Autodesk Fusion 360 part; units mm, degrees
(part 2 of 2)
  circle A960 centre (51.0366, 22.3571) radius 0.5
  circle A961 centre (54.3293, 22.3571) radius 0.5
  circle A962 centre (57.622, 22.3571) radius 0.5
  circle A963 centre (60.9146, 22.3571) radius 0.5
  circle A964 centre (64.2073, 22.3571) radius 0.5
  circle A965 centre (67.5, 22.3571) radius 0.5
  circle A966 centre (-67.5, 25.2143) radius 0.5
  circle A967 centre (-64.2073, 25.2143) radius 0.5
  circle A968 centre (-60.9146, 25.2143) radius 0.5
  circle A969 centre (-57.622, 25.2143) radius 0.5
  circle A970 centre (-54.3293, 25.2143) radius 0.5
  circle A971 centre (-51.0366, 25.2143) radius 0.5
  circle A972 centre (-47.7439, 25.2143) radius 0.5
  circle A973 centre (-44.4512, 25.2143) radius 0.5
  circle A974 centre (-41.1585, 25.2143) radius 0.5
  circle A975 centre (-37.8659, 25.2143) radius 0.5
  circle A976 centre (-34.5732, 25.2143) radius 0.5
  circle A977 centre (-31.2805, 25.2143) radius 0.5
  circle A978 centre (-27.9878, 25.2143) radius 0.5
  circle A979 centre (-24.6951, 25.2143) radius 0.5
  circle A980 centre (-21.4024, 25.2143) radius 0.5
  circle A981 centre (-18.1098, 25.2143) radius 0.5
  circle A982 centre (-14.8171, 25.2143) radius 0.5
  circle A983 centre (-11.5244, 25.2143) radius 0.5
  circle A984 centre (-8.2317, 25.2143) radius 0.5
  circle A985 centre (-4.939, 25.2143) radius 0.5
  circle A986 centre (-1.6463, 25.2143) radius 0.5
  circle A987 centre (1.6463, 25.2143) radius 0.5
  circle A988 centre (4.939, 25.2143) radius 0.5
  circle A989 centre (8.2317, 25.2143) radius 0.5
  circle A990 centre (11.5244, 25.2143) radius 0.5
  circle A991 centre (14.8171, 25.2143) radius 0.5
  circle A992 centre (18.1098, 25.2143) radius 0.5
  circle A993 centre (21.4024, 25.2143) radius 0.5
  circle A994 centre (24.6951, 25.2143) radius 0.5
  circle A995 centre (27.9878, 25.2143) radius 0.5
  circle A996 centre (31.2805, 25.2143) radius 0.5
  circle A997 centre (34.5732, 25.2143) radius 0.5
  circle A998 centre (37.8659, 25.2143) radius 0.5
  circle A999 centre (41.1585, 25.2143) radius 0.5
  circle A1000 centre (44.4512, 25.2143) radius 0.5
  circle A1001 centre (47.7439, 25.2143) radius 0.5
  circle A1002 centre (51.0366, 25.2143) radius 0.5
  circle A1003 centre (54.3293, 25.2143) radius 0.5
  circle A1004 centre (57.622, 25.2143) radius 0.5
  circle A1005 centre (60.9146, 25.2143) radius 0.5
  circle A1006 centre (64.2073, 25.2143) radius 0.5
  circle A1007 centre (67.5, 25.2143) radius 0.5
  circle A1008 centre (-67.5, 28.0714) radius 0.5
  circle A1009 centre (-64.2073, 28.0714) radius 0.5
  circle A1010 centre (-60.9146, 28.0714) radius 0.5
  circle A1011 centre (-57.622, 28.0714) radius 0.5
  circle A1012 centre (-54.3293, 28.0714) radius 0.5
  circle A1013 centre (-51.0366, 28.0714) radius 0.5
  circle A1014 centre (-47.7439, 28.0714) radius 0.5
  circle A1015 centre (-44.4512, 28.0714) radius 0.5
  circle A1016 centre (-41.1585, 28.0714) radius 0.5
  circle A1017 centre (-37.8659, 28.0714) radius 0.5
  circle A1018 centre (-34.5732, 28.0714) radius 0.5
  circle A1019 centre (-31.2805, 28.0714) radius 0.5
  circle A1020 centre (-27.9878, 28.0714) radius 0.5
  circle A1021 centre (-24.6951, 28.0714) radius 0.5
  circle A1022 centre (-21.4024, 28.0714) radius 0.5
  circle A1023 centre (-18.1098, 28.0714) radius 0.5
  circle A1024 centre (-14.8171, 28.0714) radius 0.5
  circle A1025 centre (-11.5244, 28.0714) radius 0.5
  circle A1026 centre (-8.2317, 28.0714) radius 0.5
  circle A1027 centre (-4.939, 28.0714) radius 0.5
  circle A1028 centre (-1.6463, 28.0714) radius 0.5
  circle A1029 centre (1.6463, 28.0714) radius 0.5
  circle A1030 centre (4.939, 28.0714) radius 0.5
  circle A1031 centre (8.2317, 28.0714) radius 0.5
  circle A1032 centre (11.5244, 28.0714) radius 0.5
  circle A1033 centre (14.8171, 28.0714) radius 0.5
  circle A1034 centre (18.1098, 28.0714) radius 0.5
  circle A1035 centre (21.4024, 28.0714) radius 0.5
  circle A1036 centre (24.6951, 28.0714) radius 0.5
  circle A1037 centre (27.9878, 28.0714) radius 0.5
  circle A1038 centre (31.2805, 28.0714) radius 0.5
  circle A1039 centre (34.5732, 28.0714) radius 0.5
  circle A1040 centre (37.8659, 28.0714) radius 0.5
  circle A1041 centre (41.1585, 28.0714) radius 0.5
  circle A1042 centre (44.4512, 28.0714) radius 0.5
  circle A1043 centre (47.7439, 28.0714) radius 0.5
  circle A1044 centre (51.0366, 28.0714) radius 0.5
  circle A1045 centre (54.3293, 28.0714) radius 0.5
  circle A1046 centre (57.622, 28.0714) radius 0.5
  circle A1047 centre (60.9146, 28.0714) radius 0.5
  circle A1048 centre (64.2073, 28.0714) radius 0.5
  circle A1049 centre (67.5, 28.0714) radius 0.5
  circle A1050 centre (-67.5, 30.9286) radius 0.5
  circle A1051 centre (-64.2073, 30.9286) radius 0.5
  circle A1052 centre (-60.9146, 30.9286) radius 0.5
  circle A1053 centre (-57.622, 30.9286) radius 0.5
  circle A1054 centre (-54.3293, 30.9286) radius 0.5
  circle A1055 centre (-51.0366, 30.9286) radius 0.5
  circle A1056 centre (-47.7439, 30.9286) radius 0.5
  circle A1057 centre (-44.4512, 30.9286) radius 0.5
  circle A1058 centre (-41.1585, 30.9286) radius 0.5
  circle A1059 centre (-37.8659, 30.9286) radius 0.5
  circle A1060 centre (-34.5732, 30.9286) radius 0.5
  circle A1061 centre (-31.2805, 30.9286) radius 0.5
  circle A1062 centre (-27.9878, 30.9286) radius 0.5
  circle A1063 centre (-24.6951, 30.9286) radius 0.5
  circle A1064 centre (-21.4024, 30.9286) radius 0.5
  circle A1065 centre (-18.1098, 30.9286) radius 0.5
  circle A1066 centre (-14.8171, 30.9286) radius 0.5
  circle A1067 centre (-11.5244, 30.9286) radius 0.5
  circle A1068 centre (-8.2317, 30.9286) radius 0.5
  circle A1069 centre (-4.939, 30.9286) radius 0.5
  circle A1070 centre (-1.6463, 30.9286) radius 0.5
  circle A1071 centre (1.6463, 30.9286) radius 0.5
  circle A1072 centre (4.939, 30.9286) radius 0.5
  circle A1073 centre (8.2317, 30.9286) radius 0.5
  circle A1074 centre (11.5244, 30.9286) radius 0.5
  circle A1075 centre (14.8171, 30.9286) radius 0.5
  circle A1076 centre (18.1098, 30.9286) radius 0.5
  circle A1077 centre (21.4024, 30.9286) radius 0.5
  circle A1078 centre (24.6951, 30.9286) radius 0.5
  circle A1079 centre (27.9878, 30.9286) radius 0.5
  circle A1080 centre (31.2805, 30.9286) radius 0.5
  circle A1081 centre (34.5732, 30.9286) radius 0.5
  circle A1082 centre (37.8659, 30.9286) radius 0.5
  circle A1083 centre (41.1585, 30.9286) radius 0.5
  circle A1084 centre (44.4512, 30.9286) radius 0.5
  circle A1085 centre (47.7439, 30.9286) radius 0.5
  circle A1086 centre (51.0366, 30.9286) radius 0.5
  circle A1087 centre (54.3293, 30.9286) radius 0.5
  circle A1088 centre (57.622, 30.9286) radius 0.5
  circle A1089 centre (60.9146, 30.9286) radius 0.5
  circle A1090 centre (64.2073, 30.9286) radius 0.5
  circle A1091 centre (67.5, 30.9286) radius 0.5
  circle A1092 centre (-67.5, 33.7857) radius 0.5
  circle A1093 centre (-64.2073, 33.7857) radius 0.5
  circle A1094 centre (-60.9146, 33.7857) radius 0.5
  circle A1095 centre (-57.622, 33.7857) radius 0.5
  circle A1096 centre (-54.3293, 33.7857) radius 0.5
  circle A1097 centre (-51.0366, 33.7857) radius 0.5
  circle A1098 centre (-47.7439, 33.7857) radius 0.5
  circle A1099 centre (-44.4512, 33.7857) radius 0.5
  circle A1100 centre (-41.1585, 33.7857) radius 0.5
  circle A1101 centre (-37.8659, 33.7857) radius 0.5
  circle A1102 centre (-34.5732, 33.7857) radius 0.5
  circle A1103 centre (-31.2805, 33.7857) radius 0.5
  circle A1104 centre (-27.9878, 33.7857) radius 0.5
  circle A1105 centre (-24.6951, 33.7857) radius 0.5
  circle A1106 centre (-21.4024, 33.7857) radius 0.5
  circle A1107 centre (-18.1098, 33.7857) radius 0.5
  circle A1108 centre (-14.8171, 33.7857) radius 0.5
  circle A1109 centre (-11.5244, 33.7857) radius 0.5
  circle A1110 centre (-8.2317, 33.7857) radius 0.5
  circle A1111 centre (-4.939, 33.7857) radius 0.5
  circle A1112 centre (-1.6463, 33.7857) radius 0.5
  circle A1113 centre (1.6463, 33.7857) radius 0.5
  circle A1114 centre (4.939, 33.7857) radius 0.5
  circle A1115 centre (8.2317, 33.7857) radius 0.5
  circle A1116 centre (11.5244, 33.7857) radius 0.5
  circle A1117 centre (14.8171, 33.7857) radius 0.5
  circle A1118 centre (18.1098, 33.7857) radius 0.5
  circle A1119 centre (21.4024, 33.7857) radius 0.5
  circle A1120 centre (24.6951, 33.7857) radius 0.5
  circle A1121 centre (27.9878, 33.7857) radius 0.5
  circle A1122 centre (31.2805, 33.7857) radius 0.5
  circle A1123 centre (34.5732, 33.7857) radius 0.5
  circle A1124 centre (37.8659, 33.7857) radius 0.5
  circle A1125 centre (41.1585, 33.7857) radius 0.5
  circle A1126 centre (44.4512, 33.7857) radius 0.5
  circle A1127 centre (47.7439, 33.7857) radius 0.5
  circle A1128 centre (51.0366, 33.7857) radius 0.5
  circle A1129 centre (54.3293, 33.7857) radius 0.5
  circle A1130 centre (57.622, 33.7857) radius 0.5
  circle A1131 centre (60.9146, 33.7857) radius 0.5
  circle A1132 centre (64.2073, 33.7857) radius 0.5
  circle A1133 centre (67.5, 33.7857) radius 0.5
  circle A1134 centre (-67.5, 36.6429) radius 0.5
  circle A1135 centre (-64.2073, 36.6429) radius 0.5
  circle A1136 centre (-60.9146, 36.6429) radius 0.5
  circle A1137 centre (-57.622, 36.6429) radius 0.5
  circle A1138 centre (-54.3293, 36.6429) radius 0.5
  circle A1139 centre (-51.0366, 36.6429) radius 0.5
  circle A1140 centre (-47.7439, 36.6429) radius 0.5
  circle A1141 centre (-44.4512, 36.6429) radius 0.5
  circle A1142 centre (-41.1585, 36.6429) radius 0.5
  circle A1143 centre (-37.8659, 36.6429) radius 0.5
  circle A1144 centre (-34.5732, 36.6429) radius 0.5
  circle A1145 centre (-31.2805, 36.6429) radius 0.5
  circle A1146 centre (-27.9878, 36.6429) radius 0.5
  circle A1147 centre (-24.6951, 36.6429) radius 0.5
  circle A1148 centre (-21.4024, 36.6429) radius 0.5
  circle A1149 centre (-18.1098, 36.6429) radius 0.5
  circle A1150 centre (-14.8171, 36.6429) radius 0.5
  circle A1151 centre (-11.5244, 36.6429) radius 0.5
  circle A1152 centre (-8.2317, 36.6429) radius 0.5
  circle A1153 centre (-4.939, 36.6429) radius 0.5
  circle A1154 centre (-1.6463, 36.6429) radius 0.5
  circle A1155 centre (1.6463, 36.6429) radius 0.5
  circle A1156 centre (4.939, 36.6429) radius 0.5
  circle A1157 centre (8.2317, 36.6429) radius 0.5
  circle A1158 centre (11.5244, 36.6429) radius 0.5
  circle A1159 centre (14.8171, 36.6429) radius 0.5
  circle A1160 centre (18.1098, 36.6429) radius 0.5
  circle A1161 centre (21.4024, 36.6429) radius 0.5
  circle A1162 centre (24.6951, 36.6429) radius 0.5
  circle A1163 centre (27.9878, 36.6429) radius 0.5
  circle A1164 centre (31.2805, 36.6429) radius 0.5
  circle A1165 centre (34.5732, 36.6429) radius 0.5
  circle A1166 centre (37.8659, 36.6429) radius 0.5
  circle A1167 centre (41.1585, 36.6429) radius 0.5
  circle A1168 centre (44.4512, 36.6429) radius 0.5
  circle A1169 centre (47.7439, 36.6429) radius 0.5
  circle A1170 centre (51.0366, 36.6429) radius 0.5
  circle A1171 centre (54.3293, 36.6429) radius 0.5
  circle A1172 centre (57.622, 36.6429) radius 0.5
  circle A1173 centre (60.9146, 36.6429) radius 0.5
  circle A1174 centre (64.2073, 36.6429) radius 0.5
  circle A1175 centre (67.5, 36.6429) radius 0.5
  circle A1176 centre (-67.5, 39.5) radius 0.5
  circle A1177 centre (-64.2073, 39.5) radius 0.5
  circle A1178 centre (-60.9146, 39.5) radius 0.5
  circle A1179 centre (-57.622, 39.5) radius 0.5
  circle A1180 centre (-54.3293, 39.5) radius 0.5
  circle A1181 centre (-51.0366, 39.5) radius 0.5
  circle A1182 centre (-47.7439, 39.5) radius 0.5
  circle A1183 centre (-44.4512, 39.5) radius 0.5
  circle A1184 centre (-41.1585, 39.5) radius 0.5
  circle A1185 centre (-37.8659, 39.5) radius 0.5
  circle A1186 centre (-34.5732, 39.5) radius 0.5
  circle A1187 centre (-31.2805, 39.5) radius 0.5
  circle A1188 centre (-27.9878, 39.5) radius 0.5
  circle A1189 centre (-24.6951, 39.5) radius 0.5
  circle A1190 centre (-21.4024, 39.5) radius 0.5
  circle A1191 centre (-18.1098, 39.5) radius 0.5
  circle A1192 centre (-14.8171, 39.5) radius 0.5
  circle A1193 centre (-11.5244, 39.5) radius 0.5
  circle A1194 centre (-8.2317, 39.5) radius 0.5
  circle A1195 centre (-4.939, 39.5) radius 0.5
  circle A1196 centre (-1.6463, 39.5) radius 0.5
  circle A1197 centre (1.6463, 39.5) radius 0.5
  circle A1198 centre (4.939, 39.5) radius 0.5
  circle A1199 centre (8.2317, 39.5) radius 0.5
  circle A1200 centre (11.5244, 39.5) radius 0.5
  circle A1201 centre (14.8171, 39.5) radius 0.5
  circle A1202 centre (18.1098, 39.5) radius 0.5
  circle A1203 centre (21.4024, 39.5) radius 0.5
  circle A1204 centre (24.6951, 39.5) radius 0.5
  circle A1205 centre (27.9878, 39.5) radius 0.5
  circle A1206 centre (31.2805, 39.5) radius 0.5
  circle A1207 centre (34.5732, 39.5) radius 0.5
  circle A1208 centre (37.8659, 39.5) radius 0.5
  circle A1209 centre (41.1585, 39.5) radius 0.5
  circle A1210 centre (44.4512, 39.5) radius 0.5
  circle A1211 centre (47.7439, 39.5) radius 0.5
  circle A1212 centre (51.0366, 39.5) radius 0.5
  circle A1213 centre (54.3293, 39.5) radius 0.5
  circle A1214 centre (57.622, 39.5) radius 0.5
  circle A1215 centre (60.9146, 39.5) radius 0.5
  circle A1216 centre (64.2073, 39.5) radius 0.5
  circle A1217 centre (67.5, 39.5) radius 0.5
  dimension "d5" = 82
  dimension "d6" = 136
  dimension "d9" = 135
  dimension "d10" = 80
  constraint vertical L0
  constraint perpendicular L0 L1
  constraint perpendicular L1 L2
  constraint perpendicular L0 L3
  constraint symmetric L0 L2 L4
  constraint symmetric L1 L3 L5
  constraint tangent L0 A0
  measures "d5" distance of L0.start L0.end
  measures "d6" distance of L0.end L1.end
extrude "拉伸2" add sketch "草图2" along normal blind 1 separate body contours L0 L3 L4 L5 | L2 L3 L4 L5 | L1 L2 L4 L5 A41 A629 | L0 L1 L4 L5 A0 A588 makes body 2
